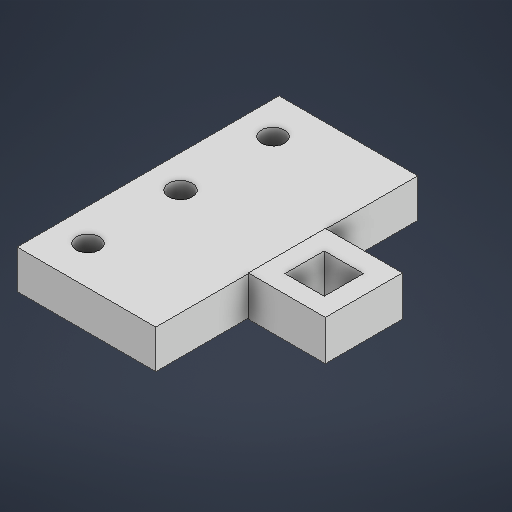
# Autodesk Inventor part: top_holder
Saved by Autodesk Inventor 2027.1 (Build 311270010, 270A)
## iProperties
Created: 2026-10-08
Part Number: top_holder
Material: Generic
Document SubType Name: Modeling
Designer: khaar
Density: 1 g/cm^3
Appearance: Default
Author: khaar
Autodesk Inventor part; units mm, degrees
ref_plane "YZ Plane" through (0, 0, 0) normal (1, 0, 0) x (0, 1, 0)
ref_plane "XZ Plane" through (0, 0, 0) normal (0, 1, 0) x (-1, 0, 0)
ref_plane "XY Plane" through (0, 0, 0) normal (0, 0, 1) x (1, 0, 0)
sketch "Sketch1" plane through (0, 0, 0) normal (0, 1, 0) x (-1, 0, 0)
  line L0 (45, 85) -> (-45, 85)
  line L1 (-45, 85) -> (-45, -85)
  line L2 (-45, -85) -> (45, -85)
  line L3 (45, -85) -> (45, 85)
  line L4 (45, 85) -> (-45, -85) construction
  line L5 (-45, 85) -> (45, -85) construction
  point P0 (0, 0)
  dimension "d0" = 170
  dimension "d1" = 90
  constraints: 12 end point, 2 midpoint, 2 parallel, 1 horizontal, 1 perpendicular
  measures "d0" distance of L2.end L0.start
  measures "d1" distance of L1.end L2.end
extrude "Extrusion1" add sketch "Sketch1" along normal blind 25
sketch "Sketch2" plane through (0, 25, 0) normal (0, 1, 0) x (1, 0, 0)
  circle A0 centre (-24, 0) radius 7.7
  circle A1 centre (-24, 60) radius 7.5
  circle A2 centre (-24, -60) radius 7.5
  line L0 (-45, -85) -> (45, -85) projected
  line L1 (45, 85) -> (-45, 85) projected
  line L2 (-45, 85) -> (-45, -85) projected
  point P0 (0, 0)
  dimension "d4" = 15.4
  dimension "d5" = 15
  dimension "d6" = 15
  dimension "d7" = 25
  dimension "d8" = 25
  dimension "d9" = 60
  dimension "d10" = 60
  dimension "d11" = 21
  constraints: 3 centre point
  measures "d4" diameter of A0
  measures "d5" diameter of A1
  measures "d6" diameter of A2
  measures "d7" distance from line of L0 A2.centre
  measures "d8" distance from line of L1 A1.centre
  measures "d9" distance of A0.centre A2.centre
  measures "d10" distance of A1.centre A0.centre
  measures "d11" distance from line of L2 A1.centre
extrude "Extrusion2" cut sketch "Sketch2" against normal blind 15
sketch "Sketch3" plane through (45, 0, 85) normal (1, 0, 0) x (0, 0, -1)
  line L0 (0, 25) -> (170, 25) projected
  line L1 (60, 25.4566) -> (110, 25.4566)
  line L2 (110, 25.4566) -> (110, -0.5434)
  line L3 (110, -0.5434) -> (60, -0.5434)
  line L4 (60, -0.5434) -> (60, 25.4566)
  line L5 (60, 25.4566) -> (110, -0.5434) construction
  line L6 (110, 25.4566) -> (60, -0.5434) construction
  point P0 (85, 0)
  point P1 (85, 12.4566)
  point P2 (110, 25)
  point P3 (60, 25)
  dimension "d15" = 50
  dimension "d16" = 26
  constraints: 12 end point, 2 midpoint, 2 parallel, 1 horizontal, 1 perpendicular
  measures "d15" distance of L1.start L1.end
  measures "d16" distance of L1.end L2.end
extrude "Extrusion3" add sketch "Sketch3" along normal blind 50
sketch "Sketch6" plane through (45, 25.4566, 25) normal (0, 1, 0) x (1, 0, 0)
  line L0 (25, 5.6391) -> (25, 42.8337)
  line L1 (50, 50) -> (50, 0) projected
  line L2 (12.25, 11.4864) -> (37.75, 11.4864)
  line L3 (37.75, 11.4864) -> (37.75, 36.9864)
  line L4 (37.75, 36.9864) -> (12.25, 36.9864)
  line L5 (12.25, 36.9864) -> (12.25, 11.4864)
  line L6 (12.25, 11.4864) -> (37.75, 36.9864) construction
  line L7 (37.75, 11.4864) -> (12.25, 36.9864) construction
  point P0 (-45, 25)
  point P1 (25, 24.2364)
  dimension "d27" = 25
  dimension "d28" = 25.5
  dimension "d29" = 25.5
  constraints: 14 end point, 3 midpoint, 2 parallel, 1 horizontal, 1 perpendicular, 1 vertical
  measures "d27" distance between parallel lines of L1 L0
  measures "d28" distance of L4.end L2.start
  measures "d29" distance of L3.end L4.end
extrude "Extrusion5" cut sketch "Sketch6" against normal blind 30
equation "\"d12\" = d6"
body "Solid1"
